Autodesk Fusion 360 part; units mm, degrees
(part 6 of 7)
  spline S19 degree 5 poles (-2.142617, 4.378906) (-2.143607, 4.374892) (-2.145571, 4.366867) (-2.148475, 4.354836) (-2.152259, 4.338808) (-2.156842, 4.318795) (-2.16128, 4.298806) (-2.165572, 4.27884) (-2.169716, 4.258897) (-2.173714, 4.23898) (-2.177564, 4.219088) (-2.181267, 4.199223) (-2.184822, 4.179387) (-2.188228, 4.15958) (-2.191486, 4.139805) (-2.194596, 4.12006) (-2.197556, 4.100349) (-2.200366, 4.080671) (-2.203027, 4.061028) (-2.205537, 4.041421) (-2.207897, 4.021851) (-2.210105, 4.002319) (-2.212162, 3.982827) (-2.214067, 3.963375) (-2.215819, 3.943964) (-2.217418, 3.924597) (-2.218864, 3.905273) (-2.220156, 3.885995) (-2.221294, 3.866763) (-2.222277, 3.847579) (-2.223104, 3.828444) (-2.223774, 3.80936) (-2.224287, 3.790328) (-2.224642, 3.771349) (-2.224838, 3.752425) (-2.224875, 3.733556) (-2.224754, 3.714745) (-2.224472, 3.695992) (-2.224029, 3.677299) (-2.223424, 3.658668) (-2.222655, 3.6401) (-2.221719, 3.621599) (-2.220614, 3.603166) (-2.219341, 3.584803) (-2.217898, 3.566511) (-2.216286, 3.548291) (-2.214508, 3.530142) (-2.212562, 3.512068) (-2.210445, 3.494069) (-2.208154, 3.47615) (-2.205679, 3.458317) (-2.203014, 3.440574) (-2.200153, 3.422926) (-2.197095, 3.405375) (-2.193845, 3.387919) (-2.190414, 3.370554) (-2.186811, 3.353277) (-2.183037, 3.336088) (-2.179085, 3.318994) (-2.174929, 3.30201) (-2.170533, 3.285156) (-2.165861, 3.268452) (-2.160894, 3.251912) (-2.155636, 3.235535) (-2.150128, 3.219302) (-2.144432, 3.203184) (-2.138596, 3.187157) (-2.132628, 3.171222) (-2.126466, 3.155419) (-2.119948, 3.139839) (-2.112853, 3.124607) (-2.106537, 3.112799) (-2.10136, 3.104201) (-2.097704, 3.098588) (-2.095824, 3.095812) knots -1 -1 -1 -1 -1 -1 -0.98571429 -0.97142857 -0.95714286 -0.94285714 -0.92857143 -0.91428571 -0.9 -0.88571429 -0.87142857 -0.85714286 -0.84285714 -0.82857143 -0.81428571 -0.8 -0.78571429 -0.77142857 -0.75714286 -0.74285714 -0.72857143 -0.71428571 -0.7 -0.68571429 -0.67142857 -0.65714286 -0.64285714 -0.62857143 -0.61428571 -0.6 -0.58571429 -0.57142857 -0.55714286 -0.54285714 -0.52857143 -0.51428571 -0.5 -0.48571429 -0.47142857 -0.45714286 -0.44285714 -0.42857143 -0.41428571 -0.4 -0.38571429 -0.37142857 -0.35714286 -0.34285714 -0.32857143 -0.31428571 -0.3 -0.28571429 -0.27142857 -0.25714286 -0.24285714 -0.22857143 -0.21428571 -0.2 -0.18571429 -0.17142857 -0.15714286 -0.14285714 -0.12857143 -0.11428571 -0.1 -0.08571429 -0.07142857 -0.05714286 -0.04285714 -0.02857143 -0.01428571 0 0 0 0 0 0
  line L19 (-2.095824, 3.095812) -> (-1.826023, 2.69728)
  arc A20 (-1.826023, 2.69728) -> (-2.409955, 2.1913) centre (0, 0) ccw
  line L20 (-2.409955, 2.1913) -> (-2.766034, 2.515072)
  spline S20 degree 5 poles (-2.766034, 2.515072) (-2.768515, 2.517327) (-2.77355, 2.521745) (-2.781324, 2.528093) (-2.792112, 2.536025) (-2.80618, 2.545216) (-2.820673, 2.553885) (-2.835439, 2.562233) (-2.850362, 2.570408) (-2.865395, 2.578465) (-2.880539, 2.586397) (-2.895823, 2.594159) (-2.911285, 2.601695) (-2.92695, 2.608965) (-2.942818, 2.615966) (-2.958875, 2.622717) (-2.975095, 2.629247) (-2.991453, 2.635592) (-3.00793, 2.641773) (-3.024518, 2.647799) (-3.041218, 2.653666) (-3.058034, 2.659367) (-3.074971, 2.664892) (-3.092032, 2.670235) (-3.109215, 2.675398) (-3.126515, 2.680386) (-3.143925, 2.685204) (-3.16144, 2.68986) (-3.179053, 2.694359) (-3.196764, 2.698702) (-3.21457, 2.70289) (-3.23247, 2.706922) (-3.250465, 2.710796) (-3.268553, 2.714512) (-3.286733, 2.718072) (-3.305001, 2.721476) (-3.323357, 2.724726) (-3.341797, 2.727825) (-3.360319, 2.730772) (-3.378921, 2.73357) (-3.397603, 2.736218) (-3.416363, 2.738717) (-3.435199, 2.741067) (-3.45411, 2.743268) (-3.473096, 2.74532) (-3.492154, 2.747225) (-3.511282, 2.748982) (-3.53048, 2.750593) (-3.549746, 2.752057) (-3.569078, 2.753376) (-3.588476, 2.75455) (-3.607939, 2.755578) (-3.627464, 2.756461) (-3.647051, 2.757199) (-3.666698, 2.757793) (-3.686405, 2.758242) (-3.70617, 2.758548) (-3.725991, 2.75871) (-3.745869, 2.758728) (-3.765801, 2.758604) (-3.785786, 2.758336) (-3.805825, 2.757925) (-3.825914, 2.757372) (-3.846055, 2.756677) (-3.866244, 2.755839) (-3.886481, 2.754858) (-3.906765, 2.753736) (-3.927094, 2.752472) (-3.947468, 2.751065) (-3.967886, 2.749518) (-3.988346, 2.747828) (-4.00475, 2.746364) (-4.017072, 2.745203) (-4.025295, 2.7444) (-4.029409, 2.743992) knots 0 0 0 0 0 0 0.01428571 0.02857143 0.04285714 0.05714286 0.07142857 0.08571429 0.1 0.11428571 0.12857143 0.14285714 0.15714286 0.17142857 0.18571429 0.2 0.21428571 0.22857143 0.24285714 0.25714286 0.27142857 0.28571429 0.3 0.31428571 0.32857143 0.34285714 0.35714286 0.37142857 0.38571429 0.4 0.41428571 0.42857143 0.44285714 0.45714286 0.47142857 0.48571429 0.5 0.51428571 0.52857143 0.54285714 0.55714286 0.57142857 0.58571429 0.6 0.61428571 0.62857143 0.64285714 0.65714286 0.67142857 0.68571429 0.7 0.71428571 0.72857143 0.74285714 0.75714286 0.77142857 0.78571429 0.8 0.81428571 0.82857143 0.84285714 0.85714286 0.87142857 0.88571429 0.9 0.91428571 0.92857143 0.94285714 0.95714286 0.97142857 0.98571429 1 1 1 1 1 1
  arc A21 (-4.029409, 2.743992) -> (-4.1699, 2.525384) centre (0, 0) ccw
  spline S21 degree 5 poles (-4.1699, 2.525384) (-4.168562, 2.521472) (-4.165876, 2.513659) (-4.161814, 2.501968) (-4.156332, 2.486438) (-4.149368, 2.467125) (-4.142295, 2.447909) (-4.13511, 2.428793) (-4.127815, 2.409775) (-4.12041, 2.390858) (-4.112895, 2.372043) (-4.10527, 2.35333) (-4.097536, 2.33472) (-4.089694, 2.316216) (-4.081743, 2.297818) (-4.073684, 2.279527) (-4.065518, 2.261345) (-4.057243, 2.243271) (-4.048862, 2.225308) (-4.040373, 2.207456) (-4.031778, 2.189717) (-4.023076, 2.172092) (-4.014268, 2.154582) (-4.005353, 2.137188) (-3.996333, 2.119912) (-3.987208, 2.102754) (-3.977977, 2.085716) (-3.968642, 2.0688) (-3.959202, 2.052006) (-3.949657, 2.035336) (-3.940007, 2.018792) (-3.930253, 2.002375) (-3.920395, 1.986087) (-3.910433, 1.969929) (-3.900367, 1.953902) (-3.890197, 1.938009) (-3.879925, 1.92225) (-3.869549, 1.906626) (-3.85907, 1.89114) (-3.848489, 1.875793) (-3.837803, 1.860589) (-3.827013, 1.845531) (-3.816119, 1.830622) (-3.805119, 1.815862) (-3.794016, 1.801254) (-3.78281, 1.786797) (-3.771502, 1.772491) (-3.760092, 1.758338) (-3.748581, 1.744341) (-3.736966, 1.730506) (-3.725243, 1.716841) (-3.713408, 1.703356) (-3.70146, 1.690056) (-3.689398, 1.676944) (-3.677227, 1.664016) (-3.664953, 1.651263) (-3.652581, 1.638677) (-3.640113, 1.626257) (-3.627547, 1.614013) (-3.614868, 1.601972) (-3.602057, 1.59017) (-3.589097, 1.578644) (-3.575976, 1.567415) (-3.562699, 1.556481) (-3.549289, 1.545803) (-3.535783, 1.535322) (-3.522209, 1.524994) (-3.508573, 1.514816) (-3.494845, 1.504853) (-3.480939, 1.49527) (-3.466735, 1.486292) (-3.455038, 1.479774) (-3.446034, 1.475339) (-3.439924, 1.472594) (-3.436842, 1.471275) knots -1 -1 -1 -1 -1 -1 -0.98571429 -0.97142857 -0.95714286 -0.94285714 -0.92857143 -0.91428571 -0.9 -0.88571429 -0.87142857 -0.85714286 -0.84285714 -0.82857143 -0.81428571 -0.8 -0.78571429 -0.77142857 -0.75714286 -0.74285714 -0.72857143 -0.71428571 -0.7 -0.68571429 -0.67142857 -0.65714286 -0.64285714 -0.62857143 -0.61428571 -0.6 -0.58571429 -0.57142857 -0.55714286 -0.54285714 -0.52857143 -0.51428571 -0.5 -0.48571429 -0.47142857 -0.45714286 -0.44285714 -0.42857143 -0.41428571 -0.4 -0.38571429 -0.37142857 -0.35714286 -0.34285714 -0.32857143 -0.31428571 -0.3 -0.28571429 -0.27142857 -0.25714286 -0.24285714 -0.22857143 -0.21428571 -0.2 -0.18571429 -0.17142857 -0.15714286 -0.14285714 -0.12857143 -0.11428571 -0.1 -0.08571429 -0.07142857 -0.05714286 -0.04285714 -0.02857143 -0.01428571 0 0 0 0 0 0
  line L21 (-3.436842, 1.471275) -> (-2.994408, 1.281873)
  circle A22 centre (0, 0) radius 1
  circle A23 centre (0, 0) radius 3
  dimension "d44" = 6
  constraint concentric A0 A23
  measures "d44" diameter of A23
extrude "Extrude12" add sketch "Sketch16" along normal blind 0.3 contours A23 picked at (2.318441, -0.198723) bodies 3
fillet "Fillet6" radius 0.1 1 faces at (-2.985092, 0.298704, 15.6) on bodies 3
move_body "Move3" bodies 3 to x (1, 0, 0) y (0, 1, 0) z (0, 0, 1) at (0, 0, -0.4)
combine "Combine1" operation add target body 2 tool bodies 3
sketch "Base Circle (2) (2)" plane through (0, 0, 0) normal (0, 0, 1) x (1, 0, 0)
  circle A0 centre (0, 0) radius 3.9087
  circle A1 centre (0, 0) radius 1
extrude "Extrude7" [suppressed]
sketch "Gear Tooth (2) (2)" plane through (0, 0, 0) normal (0, 0, 1) x (1, 0, 0)
  spline S0 degree 5 poles (4.423269, -0.748927) (4.427248, -0.7496) (4.43522, -0.750805) (4.447221, -0.752184) (4.463304, -0.753207) (4.483525, -0.753372) (4.503836, -0.752732) (4.524213, -0.751592) (4.544635, -0.750177) (4.565089, -0.748571) (4.585573, -0.746765) (4.606086, -0.744695) (4.626631, -0.742278) (4.647207, -0.739459) (4.667813, -0.736235) (4.688444, -0.732635) (4.709097, -0.728709) (4.729766, -0.724506) (4.750447, -0.720062) (4.771138, -0.715388) (4.791838, -0.710482) (4.812545, -0.705331) (4.83326, -0.699923) (4.85398, -0.694252) (4.874704, -0.68832) (4.89543, -0.682135) (4.916157, -0.675708) (4.936882, -0.669051) (4.957604, -0.66217) (4.978321, -0.65507) (4.999031, -0.647752) (5.019735, -0.640216) (5.04043, -0.632459) (5.061115, -0.624483) (5.081789, -0.616291) (5.10245, -0.607884) (5.123098, -0.599266) (5.143731, -0.590442) (5.164348, -0.581412) (5.184947, -0.57218) (5.205527, -0.562747) (5.226088, -0.553113) (5.246628, -0.54328) (5.267145, -0.533249) (5.28764, -0.523021) (5.30811, -0.512598) (5.328555, -0.501982) (5.348973, -0.491173) (5.369363, -0.480175) (5.389725, -0.468987) (5.410057, -0.457611) (5.430358, -0.446048) (5.450628, -0.4343) (5.470864, -0.422366) (5.491067, -0.410249) (5.511234, -0.397949) (5.531366, -0.385468) (5.55146, -0.372806) (5.571516, -0.359965) (5.591534, -0.346946) (5.611511, -0.333749) (5.631448, -0.320375) (5.651343, -0.306826) (5.671196, -0.293101) (5.691004, -0.279203) (5.710767, -0.265132) (5.730484, -0.250889) (5.750154, -0.236476) (5.769776, -0.221891) (5.789348, -0.207138) (5.808872, -0.192215) (5.824452, -0.180143) (5.836116, -0.171012) (5.843881, -0.164892) (5.847761, -0.161823) knots 0 0 0 0 0 0 0.01428571 0.02857143 0.04285714 0.05714286 0.07142857 0.08571429 0.1 0.11428571 0.12857143 0.14285714 0.15714286 0.17142857 0.18571429 0.2 0.21428571 0.22857143 0.24285714 0.25714286 0.27142857 0.28571429 0.3 0.31428571 0.32857143 0.34285714 0.35714286 0.37142857 0.38571429 0.4 0.41428571 0.42857143 0.44285714 0.45714286 0.47142857 0.48571429 0.5 0.51428571 0.52857143 0.54285714 0.55714286 0.57142857 0.58571429 0.6 0.61428571 0.62857143 0.64285714 0.65714286 0.67142857 0.68571429 0.7 0.71428571 0.72857143 0.74285714 0.75714286 0.77142857 0.78571429 0.8 0.81428571 0.82857143 0.84285714 0.85714286 0.87142857 0.88571429 0.9 0.91428571 0.92857143 0.94285714 0.95714286 0.97142857 0.98571429 1 1 1 1 1 1
  spline S1 degree 5 poles (4.423269, 0.748927) (4.427248, 0.7496) (4.43522, 0.750805) (4.447221, 0.752184) (4.463304, 0.753207) (4.483525, 0.753372) (4.503836, 0.752732) (4.524213, 0.751592) (4.544635, 0.750177) (4.565089, 0.748571) (4.585573, 0.746765) (4.606086, 0.744695) (4.626631, 0.742278) (4.647207, 0.739459) (4.667813, 0.736235) (4.688444, 0.732635) (4.709097, 0.728709) (4.729766, 0.724506) (4.750447, 0.720062) (4.771138, 0.715388) (4.791838, 0.710482) (4.812545, 0.705331) (4.83326, 0.699923) (4.85398, 0.694252) (4.874704, 0.68832) (4.89543, 0.682135) (4.916157, 0.675708) (4.936882, 0.669051) (4.957604, 0.66217) (4.978321, 0.65507) (4.999031, 0.647752) (5.019735, 0.640216) (5.04043, 0.632459) (5.061115, 0.624483) (5.081789, 0.616291) (5.10245, 0.607884) (5.123098, 0.599266) (5.143731, 0.590442) (5.164348, 0.581412) (5.184947, 0.57218) (5.205527, 0.562747) (5.226088, 0.553113) (5.246628, 0.54328) (5.267145, 0.533249) (5.28764, 0.523021) (5.30811, 0.512598) (5.328555, 0.501982) (5.348973, 0.491173) (5.369363, 0.480175) (5.389725, 0.468987) (5.410057, 0.457611) (5.430358, 0.446048) (5.450628, 0.4343) (5.470864, 0.422366) (5.491067, 0.410249) (5.511234, 0.397949) (5.531366, 0.385468) (5.55146, 0.372806) (5.571516, 0.359965) (5.591534, 0.346946) (5.611511, 0.333749) (5.631448, 0.320375) (5.651343, 0.306826) (5.671196, 0.293101) (5.691004, 0.279203) (5.710767, 0.265132) (5.730484, 0.250889) (5.750154, 0.236476) (5.769776, 0.221891) (5.789348, 0.207138) (5.808872, 0.192215) (5.824452, 0.180143) (5.836116, 0.171012) (5.843881, 0.164892) (5.847761, 0.161823) knots 0 0 0 0 0 0 0.01428571 0.02857143 0.04285714 0.05714286 0.07142857 0.08571429 0.1 0.11428571 0.12857143 0.14285714 0.15714286 0.17142857 0.18571429 0.2 0.21428571 0.22857143 0.24285714 0.25714286 0.27142857 0.28571429 0.3 0.31428571 0.32857143 0.34285714 0.35714286 0.37142857 0.38571429 0.4 0.41428571 0.42857143 0.44285714 0.45714286 0.47142857 0.48571429 0.5 0.51428571 0.52857143 0.54285714 0.55714286 0.57142857 0.58571429 0.6 0.61428571 0.62857143 0.64285714 0.65714286 0.67142857 0.68571429 0.7 0.71428571 0.72857143 0.74285714 0.75714286 0.77142857 0.78571429 0.8 0.81428571 0.82857143 0.84285714 0.85714286 0.87142857 0.88571429 0.9 0.91428571 0.92857143 0.94285714 0.95714286 0.97142857 0.98571429 1 1 1 1 1 1
  arc A0 (5.847761, -0.161823) -> (5.847761, 0.161823) centre (0, 0) ccw
  line L0 (3.84399, -0.650846) -> (4.423269, -0.748927)
  line L1 (3.84399, 0.650846) -> (4.423269, 0.748927)
  line L2 (3.84399, -0.650846) -> (3.84399, 0.650846)
  point P0 (4.521581, -0.751683)
  point P1 (4.62174, -0.742791)
  point P2 (4.723012, -0.725845)
  point P3 (4.82507, -0.702027)
  point P4 (4.927679, -0.671978)
  point P5 (5.030643, -0.636099)
  point P6 (5.133785, -0.594669)
  point P7 (5.236942, -0.547891)
  point P8 (5.339959, -0.495919)
  point P9 (5.442684, -0.438878)
  point P10 (5.54497, -0.376867)
  point P11 (5.646673, -0.309973)
  point P12 (5.747651, -0.23827)
  point P13 (4.521581, 0.751683)
  point P14 (4.62174, 0.742791)
  point P15 (4.723012, 0.725845)
  point P16 (4.82507, 0.702027)
  point P17 (4.927679, 0.671978)
  point P18 (5.030643, 0.636099)
  point P19 (5.133785, 0.594669)
  point P20 (5.236942, 0.547891)
  point P21 (5.339959, 0.495919)
  point P22 (5.442684, 0.438878)
  point P23 (5.54497, 0.376867)
  point P24 (5.646673, 0.309973)
  point P25 (5.747651, 0.23827)
extrude "Extrude8" [suppressed]
pattern_circular "C-Pattern3" [suppressed]
sketch "Diametrial Pitch Circle (2) (2)" plane through (0, 0, 0) normal (0, 0, 1) x (1, 0, 0)
  circle A0 centre (0, 0) radius 4.95 construction
move_body "Move1" [suppressed]
sketch "Sketch12" plane through (0, 0, 15.5) normal (0, 0, 1) x (-1, 0, 0)
  arc A0 (-3.594841, 1.534618) -> (-3.85385, 0.652515) centre (0, 0) ccw
  line L0 (-3.85385, 0.652515) -> (-4.423269, 0.748927)
  spline S0 degree 5 poles (-4.423269, 0.748927) (-4.427248, 0.7496) (-4.43522, 0.750805) (-4.447221, 0.752184) (-4.463304, 0.753207) (-4.483525, 0.753372) (-4.503836, 0.752732) (-4.524213, 0.751592) (-4.544635, 0.750177) (-4.565089, 0.748571) (-4.585573, 0.746765) (-4.606086, 0.744695) (-4.626631, 0.742278) (-4.647207, 0.739459) (-4.667813, 0.736235) (-4.688444, 0.732635) (-4.709097, 0.728709) (-4.729766, 0.724506) (-4.750447, 0.720062) (-4.771138, 0.715388) (-4.791838, 0.710482) (-4.812545, 0.705331) (-4.83326, 0.699923) (-4.85398, 0.694252) (-4.874704, 0.68832) (-4.89543, 0.682135) (-4.916157, 0.675708) (-4.936882, 0.669051) (-4.957604, 0.66217) (-4.978321, 0.65507) (-4.999031, 0.647752) (-5.019735, 0.640216) (-5.04043, 0.632459) (-5.061115, 0.624483) (-5.081789, 0.616291) (-5.10245, 0.607884) (-5.123098, 0.599266) (-5.143731, 0.590442) (-5.164348, 0.581412) (-5.184947, 0.57218) (-5.205527, 0.562747) (-5.226088, 0.553113) (-5.246628, 0.54328) (-5.267145, 0.533249) (-5.28764, 0.523021) (-5.30811, 0.512598) (-5.328555, 0.501982) (-5.348973, 0.491173) (-5.369363, 0.480175) (-5.389725, 0.468987) (-5.410057, 0.457611) (-5.430358, 0.446048) (-5.450628, 0.4343) (-5.470864, 0.422366) (-5.491067, 0.410249) (-5.511234, 0.397949) (-5.531366, 0.385468) (-5.55146, 0.372806) (-5.571516, 0.359965) (-5.591534, 0.346946) (-5.611511, 0.333749) (-5.631448, 0.320375) (-5.651343, 0.306826) (-5.671196, 0.293101) (-5.691004, 0.279203) (-5.710767, 0.265132) (-5.730484, 0.250889) (-5.750154, 0.236476) (-5.769776, 0.221891) (-5.789348, 0.207138) (-5.808872, 0.192215) (-5.824452, 0.180143) (-5.836116, 0.171012) (-5.843881, 0.164892) (-5.847761, 0.161823) knots 0 0 0 0 0 0 0.01428571 0.02857143 0.04285714 0.05714286 0.07142857 0.08571429 0.1 0.11428571 0.12857143 0.14285714 0.15714286 0.17142857 0.18571429 0.2 0.21428571 0.22857143 0.24285714 0.25714286 0.27142857 0.28571429 0.3 0.31428571 0.32857143 0.34285714 0.35714286 0.37142857 0.38571429 0.4 0.41428571 0.42857143 0.44285714 0.45714286 0.47142857 0.48571429 0.5 0.51428571 0.52857143 0.54285714 0.55714286 0.57142857 0.58571429 0.6 0.61428571 0.62857143 0.64285714 0.65714286 0.67142857 0.68571429 0.7 0.71428571 0.72857143 0.74285714 0.75714286 0.77142857 0.78571429 0.8 0.81428571 0.82857143 0.84285714 0.85714286 0.87142857 0.88571429 0.9 0.91428571 0.92857143 0.94285714 0.95714286 0.97142857 0.98571429 1 1 1 1 1 1
  arc A1 (-5.847761, 0.161823) -> (-5.847761, -0.161823) centre (0, 0) ccw
  spline S1 degree 5 poles (-5.847761, -0.161823) (-5.843881, -0.164892) (-5.836116, -0.171012) (-5.824452, -0.180143) (-5.808872, -0.192215) (-5.789348, -0.207138) (-5.769776, -0.221891) (-5.750154, -0.236476) (-5.730484, -0.250889) (-5.710767, -0.265132) (-5.691004, -0.279203) (-5.671196, -0.293101) (-5.651343, -0.306826) (-5.631448, -0.320375) (-5.611511, -0.333749) (-5.591534, -0.346946) (-5.571516, -0.359965) (-5.55146, -0.372806) (-5.531366, -0.385468) (-5.511234, -0.397949) (-5.491067, -0.410249) (-5.470864, -0.422366) (-5.450628, -0.4343) (-5.430358, -0.446048) (-5.410057, -0.457611) (-5.389725, -0.468987) (-5.369363, -0.480175) (-5.348973, -0.491173) (-5.328555, -0.501982) (-5.30811, -0.512598) (-5.28764, -0.523021) (-5.267145, -0.533249) (-5.246628, -0.54328) (-5.226088, -0.553113) (-5.205527, -0.562747) (-5.184947, -0.57218) (-5.164348, -0.581412) (-5.143731, -0.590442) (-5.123098, -0.599266) (-5.10245, -0.607884) (-5.081789, -0.616291) (-5.061115, -0.624483) (-5.04043, -0.632459) (-5.019735, -0.640216) (-4.999031, -0.647752) (-4.978321, -0.65507) (-4.957604, -0.66217) (-4.936882, -0.669051) (-4.916157, -0.675708) (-4.89543, -0.682135) (-4.874704, -0.68832) (-4.85398, -0.694252) (-4.83326, -0.699923) (-4.812545, -0.705331) (-4.791838, -0.710482) (-4.771138, -0.715388) (-4.750447, -0.720062) (-4.729766, -0.724506) (-4.709097, -0.728709) (-4.688444, -0.732635) (-4.667813, -0.736235) (-4.647207, -0.739459) (-4.626631, -0.742278) (-4.606086, -0.744695) (-4.585573, -0.746765) (-4.565089, -0.748571) (-4.544635, -0.750177) (-4.524213, -0.751592) (-4.503836, -0.752732) (-4.483525, -0.753372) (-4.463304, -0.753207) (-4.447221, -0.752184) (-4.43522, -0.750805) (-4.427248, -0.7496) (-4.423269, -0.748927) knots -1 -1 -1 -1 -1 -1 -0.98571429 -0.97142857 -0.95714286 -0.94285714 -0.92857143 -0.91428571 -0.9 -0.88571429 -0.87142857 -0.85714286 -0.84285714 -0.82857143 -0.81428571 -0.8 -0.78571429 -0.77142857 -0.75714286 -0.74285714 -0.72857143 -0.71428571 -0.7 -0.68571429 -0.67142857 -0.65714286 -0.64285714 -0.62857143 -0.61428571 -0.6 -0.58571429 -0.57142857 -0.55714286 -0.54285714 -0.52857143 -0.51428571 -0.5 -0.48571429 -0.47142857 -0.45714286 -0.44285714 -0.42857143 -0.41428571 -0.4 -0.38571429 -0.37142857 -0.35714286 -0.34285714 -0.32857143 -0.31428571 -0.3 -0.28571429 -0.27142857 -0.25714286 -0.24285714 -0.22857143 -0.21428571 -0.2 -0.18571429 -0.17142857 -0.15714286 -0.14285714 -0.12857143 -0.11428571 -0.1 -0.08571429 -0.07142857 -0.05714286 -0.04285714 -0.02857143 -0.01428571 0 0 0 0 0 0
  line L1 (-4.423269, -0.748927) -> (-3.85385, -0.652515)
  arc A2 (-3.85385, -0.652515) -> (-3.594841, -1.534618) centre (0, 0) ccw
  line L2 (-3.594841, -1.534618) -> (-4.125991, -1.761363)
  spline S2 degree 5 poles (-4.125991, -1.761363) (-4.129703, -1.762947) (-4.13706, -1.766244) (-4.147902, -1.771572) (-4.161985, -1.779406) (-4.179085, -1.7902) (-4.195826, -1.801719) (-4.212352, -1.813695) (-4.228766, -1.825926) (-4.245105, -1.838336) (-4.261361, -1.850929) (-4.277499, -1.863761) (-4.293475, -1.876901) (-4.309261, -1.890397) (-4.324852, -1.90425) (-4.340263, -1.918432) (-4.355514, -1.932901) (-4.370629, -1.947611) (-4.385625, -1.962531) (-4.400505, -1.977649) (-4.415266, -1.992968) (-4.429902, -2.008496) (-4.444404, -2.024244) (-4.458769, -2.040217) (-4.472996, -2.056412) (-4.487088, -2.072821) (-4.50105, -2.089433) (-4.514886, -2.106239) (-4.528598, -2.12323) (-4.542188, -2.140403) (-4.555654, -2.157756) (-4.568996, -2.17529) (-4.582212, -2.193003) (-4.595302, -2.210896) (-4.608265, -2.228966) (-4.621101, -2.247208) (-4.633812, -2.265621) (-4.646399, -2.2842) (-4.658861, -2.302942) (-4.671199, -2.321845) (-4.683412, -2.340908) (-4.6955, -2.360128) (-4.707463, -2.379505) (-4.719301, -2.399036) (-4.731012, -2.418721) (-4.742598, -2.438556) (-4.754057, -2.45854) (-4.765391, -2.478672) (-4.776598, -2.498948) (-4.787679, -2.519369) (-4.798633, -2.539931) (-4.80946, -2.560634) (-4.82016, -2.581476) (-4.830732, -2.602456) (-4.841177, -2.623572) (-4.851493, -2.644822) (-4.861681, -2.666206) (-4.87174, -2.687721) (-4.88167, -2.709367) (-4.891471, -2.731142) (-4.901142, -2.753045) (-4.910683, -2.775074) (-4.920095, -2.797229) (-4.929376, -2.819507) (-4.938526, -2.841908) (-4.947545, -2.864431) (-4.956431, -2.887072) (-4.965186, -2.909832) (-4.973808, -2.932709) (-4.982297, -2.955703) (-4.990654, -2.978812) (-4.997234, -2.997391) (-5.002109, -3.011378) (-5.005333, -3.020725) (-5.006938, -3.025404) knots 0 0 0 0 0 0 0.01428571 0.02857143 0.04285714 0.05714286 0.07142857 0.08571429 0.1 0.11428571 0.12857143 0.14285714 0.15714286 0.17142857 0.18571429 0.2 0.21428571 0.22857143 0.24285714 0.25714286 0.27142857 0.28571429 0.3 0.31428571 0.32857143 0.34285714 0.35714286 0.37142857 0.38571429 0.4 0.41428571 0.42857143 0.44285714 0.45714286 0.47142857 0.48571429 0.5 0.51428571 0.52857143 0.54285714 0.55714286 0.57142857 0.58571429 0.6 0.61428571 0.62857143 0.64285714 0.65714286 0.67142857 0.68571429 0.7 0.71428571 0.72857143 0.74285714 0.75714286 0.77142857 0.78571429 0.8 0.81428571 0.82857143 0.84285714 0.85714286 0.87142857 0.88571429 0.9 0.91428571 0.92857143 0.94285714 0.95714286 0.97142857 0.98571429 1 1 1 1 1 1
  arc A3 (-5.006938, -3.025404) -> (-4.831962, -3.297673) centre (0, 0) ccw
  spline S3 degree 5 poles (-4.831962, -3.297673) (-4.827038, -3.298156) (-4.817197, -3.299107) (-4.802449, -3.300482) (-4.782815, -3.302215) (-4.758323, -3.304214) (-4.73388, -3.306043) (-4.709489, -3.307704) (-4.685149, -3.309195) (-4.660862, -3.310517) (-4.636629, -3.31167) (-4.612451, -3.312652) (-4.58833, -3.313465) (-4.564268, -3.314107) (-4.540266, -3.314579) (-4.516325, -3.314881) (-4.492446, -3.315011) (-4.468631, -3.314971) (-4.444881, -3.314758) (-4.421198, -3.314374) (-4.397582, -3.313818) (-4.374036, -3.31309) (-4.35056, -3.312188) (-4.327156, -3.311113) (-4.303827, -3.309865) (-4.280572, -3.308442) (-4.257394, -3.306846) (-4.234294, -3.305074) (-4.211274, -3.303128) (-4.188335, -3.301006) (-4.165479, -3.298707) (-4.142709, -3.296231) (-4.120025, -3.293577) (-4.097429, -3.290745) (-4.074924, -3.287733) (-4.052511, -3.284542) (-4.03019, -3.281172) (-4.007965, -3.277622) (-3.985836, -3.273891) (-3.963807, -3.269977) (-3.941881, -3.265879) (-3.920059, -3.261594) (-3.898346, -3.25712) (-3.876743, -3.252457) (-3.855251, -3.247604) (-3.833872, -3.242564) (-3.812606, -3.237336) (-3.791454, -3.231921) (-3.770419, -3.226317) (-3.749508, -3.220518) (-3.728728, -3.214515) (-3.708086, -3.208302) (-3.68759, -3.201871) (-3.66724, -3.195221) (-3.647035, -3.188358) (-3.626969, -3.181295) (-3.607036, -3.17404) (-3.587235, -3.166597) (-3.567575, -3.158959) (-3.548078, -3.151096) (-3.528775, -3.14297) (-3.509698, -3.134542) (-3.490864, -3.125789) (-3.472274, -3.116715) (-3.453898, -3.107367) (-3.43569, -3.097811) (-3.417614, -3.088104) (-3.399669, -3.078254) (-3.381911, -3.068196) (-3.364477, -3.057753) (-3.347556, -3.046682) (-3.334579, -3.037126) (-3.325229, -3.029478) (-3.319174, -3.024155) (-3.316191, -3.021437) knots -1 -1 -1 -1 -1 -1 -0.98571429 -0.97142857 -0.95714286 -0.94285714 -0.92857143 -0.91428571 -0.9 -0.88571429 -0.87142857 -0.85714286 -0.84285714 -0.82857143 -0.81428571 -0.8 -0.78571429 -0.77142857 -0.75714286 -0.74285714 -0.72857143 -0.71428571 -0.7 -0.68571429 -0.67142857 -0.65714286 -0.64285714 -0.62857143 -0.61428571 -0.6 -0.58571429 -0.57142857 -0.55714286 -0.54285714 -0.52857143 -0.51428571 -0.5 -0.48571429 -0.47142857 -0.45714286 -0.44285714 -0.42857143 -0.41428571 -0.4 -0.38571429 -0.37142857 -0.35714286 -0.34285714 -0.32857143 -0.31428571 -0.3 -0.28571429 -0.27142857 -0.25714286 -0.24285714 -0.22857143 -0.21428571 -0.2 -0.18571429 -0.17142857 -0.15714286 -0.14285714 -0.12857143 -0.11428571 -0.1 -0.08571429 -0.07142857 -0.05714286 -0.04285714 -0.02857143 -0.01428571 0 0 0 0 0 0
  line L3 (-3.316191, -3.021437) -> (-2.889288, -2.632479)
  arc A4 (-2.889288, -2.632479) -> (-2.194496, -3.234521) centre (0, 0) ccw
  line L4 (-2.194496, -3.234521) -> (-2.51874, -3.712432)
  spline S4 degree 5 poles (-2.51874, -3.712432) (-2.521006, -3.715771) (-2.525413, -3.722523) (-2.531653, -3.732866) (-2.539265, -3.747071) (-2.547815, -3.765395) (-2.55567, -3.784138) (-2.563098, -3.803147) (-2.570294, -3.822311) (-2.57733, -3.841584) (-2.584197, -3.860967) (-2.590836, -3.880486) (-2.597172, -3.900178) (-2.603155, -3.920066) (-2.608782, -3.940149) (-2.614078, -3.960411) (-2.619086, -3.980829) (-2.623849, -4.001376) (-2.628398, -4.022034) (-2.632742, -4.042797) (-2.636878, -4.063664) (-2.640795, -4.08464) (-2.644481, -4.105729) (-2.64793, -4.126932) (-2.651143, -4.148248) (-2.654127, -4.169671) (-2.656891, -4.191194) (-2.659445, -4.212812) (-2.661794, -4.23452) (-2.663942, -4.256314) (-2.665889, -4.278193) (-2.667634, -4.300156) (-2.669175, -4.322203) (-2.670513, -4.344332) (-2.671649, -4.366541) (-2.672585, -4.388828) (-2.673324, -4.41119) (-2.673868, -4.433624) (-2.674219, -4.456128) (-2.674378, -4.478701) (-2.674347, -4.501341) (-2.674125, -4.524045) (-2.673713, -4.546814) (-2.673111, -4.569644) (-2.672322, -4.592536) (-2.671344, -4.615486) (-2.67018, -4.638493) (-2.668831, -4.661556) (-2.667296, -4.684673) (-2.665578, -4.707842) (-2.663677, -4.731063) (-2.661592, -4.754333) (-2.659325, -4.777651) (-2.656877, -4.801016) (-2.654247, -4.824427) (-2.651437, -4.847881) (-2.648446, -4.871378) (-2.645277, -4.894916) (-2.641928, -4.918495) (-2.6384, -4.942112) (-2.634695, -4.965766) (-2.630812, -4.989457) (-2.626751, -5.013183) (-2.622514, -5.036942) (-2.618101, -5.060734) (-2.613511, -5.084557) (-2.608746, -5.108409) (-2.603806, -5.132289) (-2.598691, -5.156195) (-2.593402, -5.180128) (-2.587938, -5.204087) (-2.583428, -5.223274) (-2.579968, -5.237676) (-2.577627, -5.247283) (-2.576447, -5.252087) knots 0 0 0 0 0 0 0.01428571 0.02857143 0.04285714 0.05714286 0.07142857 0.08571429 0.1 0.11428571 0.12857143 0.14285714 0.15714286 0.17142857 0.18571429 0.2 0.21428571 0.22857143 0.24285714 0.25714286 0.27142857 0.28571429 0.3 0.31428571 0.32857143 0.34285714 0.35714286 0.37142857 0.38571429 0.4 0.41428571 0.42857143 0.44285714 0.45714286 0.47142857 0.48571429 0.5 0.51428571 0.52857143 0.54285714 0.55714286 0.57142857 0.58571429 0.6 0.61428571 0.62857143 0.64285714 0.65714286 0.67142857 0.68571429 0.7 0.71428571 0.72857143 0.74285714 0.75714286 0.77142857 0.78571429 0.8 0.81428571 0.82857143 0.84285714 0.85714286 0.87142857 0.88571429 0.9 0.91428571 0.92857143 0.94285714 0.95714286 0.97142857 0.98571429 1 1 1 1 1 1
  arc A5 (-2.576447, -5.252087) -> (-2.282049, -5.386534) centre (0, 0) ccw
  spline S5 degree 5 poles (-2.282049, -5.386534) (-2.277645, -5.38428) (-2.268852, -5.379758) (-2.255702, -5.372942) (-2.238248, -5.363785) (-2.216563, -5.352225) (-2.195012, -5.340549) (-2.173595, -5.32876) (-2.152312, -5.316855) (-2.131166, -5.304837) (-2.110156, -5.292705) (-2.089285, -5.28046) (-2.068554, -5.268103) (-2.047965, -5.255634) (-2.027517, -5.243054) (-2.007214, -5.230365) (-1.987056, -5.217565) (-1.967043, -5.204655) (-1.947178, -5.191637) (-1.927462, -5.178509) (-1.907896, -5.165274) (-1.888481, -5.151931) (-1.86922, -5.13848) (-1.850113, -5.124923) (-1.831161, -5.11126) (-1.812367, -5.097491) (-1.793732, -5.083616) (-1.775257, -5.069638) (-1.756943, -5.055555) (-1.738793, -5.041368) (-1.720808, -5.027077) (-1.702991, -5.012683) (-1.685343, -4.998187) (-1.667866, -4.983588) (-1.650562, -4.968888) (-1.633431, -4.954086) (-1.616476, -4.939183) (-1.599698, -4.924181) (-1.5831, -4.909078) (-1.566684, -4.893876) (-1.550453, -4.878574) (-1.534413, -4.863172) (-1.518565, -4.847669) (-1.502913, -4.832067) (-1.487456, -4.816365) (-1.472196, -4.800566) (-1.457132, -4.784671) (-1.442265, -4.76868) (-1.4276, -4.752593) (-1.413144, -4.736409) (-1.398907, -4.720125) (-1.384902, -4.703738) (-1.371136, -4.687246) (-1.357612, -4.67065) (-1.344325, -4.653954) (-1.331263, -4.637163) (-1.318416, -4.620283) (-1.305782, -4.603317) (-1.293373, -4.586262) (-1.281222, -4.569107) (-1.269377, -4.551835) (-1.257884, -4.53443) (-1.246772, -4.516885) (-1.236039, -4.499201) (-1.225635, -4.481402) (-1.215483, -4.463519) (-1.205525, -4.44558) (-1.195754, -4.427592) (-1.186252, -4.40953) (-1.177232, -4.391319) (-1.168982, -4.372858) (-1.163232, -4.357803) (-1.159501, -4.346314) (-1.157285, -4.338562) (-1.156245, -4.334663) knots -1 -1 -1 -1 -1 -1 -0.98571429 -0.97142857 -0.95714286 -0.94285714 -0.92857143 -0.91428571 -0.9 -0.88571429 -0.87142857 -0.85714286 -0.84285714 -0.82857143 -0.81428571 -0.8 -0.78571429 -0.77142857 -0.75714286 -0.74285714 -0.72857143 -0.71428571 -0.7 -0.68571429 -0.67142857 -0.65714286 -0.64285714 -0.62857143 -0.61428571 -0.6 -0.58571429 -0.57142857 -0.55714286 -0.54285714 -0.52857143 -0.51428571 -0.5 -0.48571429 -0.47142857 -0.45714286 -0.44285714 -0.42857143 -0.41428571 -0.4 -0.38571429 -0.37142857 -0.35714286 -0.34285714 -0.32857143 -0.31428571 -0.3 -0.28571429 -0.27142857 -0.25714286 -0.24285714 -0.22857143 -0.21428571 -0.2 -0.18571429 -0.17142857 -0.15714286 -0.14285714 -0.12857143 -0.11428571 -0.1 -0.08571429 -0.07142857 -0.05714286 -0.04285714 -0.02857143 -0.01428571 0 0 0 0 0 0
  line L5 (-1.156245, -4.334663) -> (-1.007398, -3.77665)
  arc A6 (-1.007398, -3.77665) -> (-0.097414, -3.907486) centre (0, 0) ccw
  line L6 (-0.097414, -3.907486) -> (-0.111807, -4.48483)
  spline S6 degree 5 poles (-0.111807, -4.48483) (-0.111907, -4.488864) (-0.111965, -4.496927) (-0.111622, -4.509002) (-0.110346, -4.525067) (-0.107632, -4.545105) (-0.104108, -4.565119) (-0.100079, -4.585126) (-0.095772, -4.605138) (-0.091271, -4.625156) (-0.086569, -4.645175) (-0.0816, -4.665184) (-0.076284, -4.685175) (-0.070566, -4.705141) (-0.064442, -4.725078) (-0.057943, -4.744987) (-0.051117, -4.764871) (-0.044015, -4.784731) (-0.036673, -4.80457) (-0.029103, -4.824385) (-0.0213, -4.844176) (-0.013255, -4.86394) (-0.004955, -4.883674) (0.003608, -4.903375) (0.012429, -4.923044) (0.021501, -4.94268) (0.030812, -4.962281) (0.040351, -4.981848) (0.05011, -5.001379) (0.060086, -5.020875) (0.070277, -5.040333) (0.080684, -5.059753) (0.091306, -5.079134) (0.102145, -5.098473) (0.113196, -5.117771) (0.124458, -5.137026) (0.135926, -5.156237) (0.147597, -5.175404) (0.159469, -5.194526) (0.171539, -5.213601) (0.183805, -5.23263) (0.196267, -5.25161) (0.208923, -5.270541) (0.221772, -5.289423) (0.234812, -5.308253) (0.248042, -5.327031) (0.26146, -5.345757) (0.275064, -5.364429) (0.288853, -5.383047) (0.302825, -5.401609) (0.316978, -5.420115) (0.331313, -5.438565) (0.345826, -5.456956) (0.360518, -5.475288) (0.375387, -5.49356) (0.390432, -5.511772) (0.405651, -5.529922) (0.421043, -5.54801) (0.436608, -5.566035) (0.452344, -5.583996) (0.46825, -5.601892) (0.484325, -5.619722) (0.500567, -5.637487) (0.516977, -5.655184) (0.533553, -5.672813) (0.550293, -5.690372) (0.567197, -5.707862) (0.584264, -5.72528) (0.601492, -5.742626) (0.618881, -5.7599) (0.63643, -5.777102) (0.650597, -5.790805) (0.661294, -5.80105) (0.668458, -5.807865) (0.672048, -5.811269) knots 0 0 0 0 0 0 0.01428571 0.02857143 0.04285714 0.05714286 0.07142857 0.08571429 0.1 0.11428571 0.12857143 0.14285714 0.15714286 0.17142857 0.18571429 0.2 0.21428571 0.22857143 0.24285714 0.25714286 0.27142857 0.28571429 0.3 0.31428571 0.32857143 0.34285714 0.35714286 0.37142857 0.38571429 0.4 0.41428571 0.42857143 0.44285714 0.45714286 0.47142857 0.48571429 0.5 0.51428571 0.52857143 0.54285714 0.55714286 0.57142857 0.58571429 0.6 0.61428571 0.62857143 0.64285714 0.65714286 0.67142857 0.68571429 0.7 0.71428571 0.72857143 0.74285714 0.75714286 0.77142857 0.78571429 0.8 0.81428571 0.82857143 0.84285714 0.85714286 0.87142857 0.88571429 0.9 0.91428571 0.92857143 0.94285714 0.95714286 0.97142857 0.98571429 1 1 1 1 1 1
  arc A7 (0.672048, -5.811269) -> (0.992399, -5.76521) centre (0, 0) ccw
  spline S7 degree 5 poles (0.992399, -5.76521) (0.994884, -5.760932) (0.999837, -5.752375) (1.007215, -5.739531) (1.016948, -5.722391) (1.02894, -5.700942) (1.040758, -5.679469) (1.052401, -5.657972) (1.063869, -5.636451) (1.075161, -5.614908) (1.086276, -5.593343) (1.097213, -5.571758) (1.107973, -5.550155) (1.118553, -5.528534) (1.128953, -5.506897) (1.139173, -5.485245) (1.149211, -5.463578) (1.159067, -5.441898) (1.16874, -5.420207) (1.178229, -5.398504) (1.187534, -5.376791) (1.196652, -5.35507) (1.205584, -5.333341) (1.214329, -5.311606) (1.222885, -5.289866) (1.231251, -5.268122) (1.239427, -5.246375) (1.247412, -5.224627) (1.255205, -5.202878) (1.262803, -5.181131) (1.270207, -5.159386) (1.277414, -5.137644) (1.284423, -5.115908) (1.291233, -5.094178) (1.297843, -5.072455) (1.304251, -5.050742) (1.310458, -5.029038) (1.316461, -5.007347) (1.32226, -4.985668) (1.327851, -4.964004) (1.333232, -4.942356) (1.338399, -4.920726) (1.34335, -4.899117) (1.348082, -4.877529) (1.352596, -4.855964) (1.356892, -4.834422) (1.360971, -4.812906) (1.364832, -4.791416) (1.368472, -4.769954) (1.371884, -4.748524) (1.375056, -4.727128) (1.377979, -4.705771) (1.380644, -4.684455) (1.383048, -4.663182) (1.385199, -4.641952) (1.38711, -4.620765) (1.388792, -4.599619) (1.390247, -4.578516) (1.391466, -4.557459) (1.392413, -4.536458) (1.39304, -4.515524) (1.393299, -4.494669) (1.393161, -4.473901) (1.392629, -4.453222) (1.391759, -4.432623) (1.390631, -4.412091) (1.38931, -4.391616) (1.387804, -4.371201) (1.386033, -4.350869) (1.383776, -4.330673) (1.380735, -4.310681) (1.377433, -4.294908) (1.374361, -4.283225) (1.372034, -4.275506) (1.370801, -4.271663) knots -1 -1 -1 -1 -1 -1 -0.98571429 -0.97142857 -0.95714286 -0.94285714 -0.92857143 -0.91428571 -0.9 -0.88571429 -0.87142857 -0.85714286 -0.84285714 -0.82857143 -0.81428571 -0.8 -0.78571429 -0.77142857 -0.75714286 -0.74285714 -0.72857143 -0.71428571 -0.7 -0.68571429 -0.67142857 -0.65714286 -0.64285714 -0.62857143 -0.61428571 -0.6 -0.58571429 -0.57142857 -0.55714286 -0.54285714 -0.52857143 -0.51428571 -0.5 -0.48571429 -0.47142857 -0.45714286 -0.44285714 -0.42857143 -0.41428571 -0.4 -0.38571429 -0.37142857 -0.35714286 -0.34285714 -0.32857143 -0.31428571 -0.3 -0.28571429 -0.27142857 -0.25714286 -0.24285714 -0.22857143 -0.21428571 -0.2 -0.18571429 -0.17142857 -0.15714286 -0.14285714 -0.12857143 -0.11428571 -0.1 -0.08571429 -0.07142857 -0.05714286 -0.04285714 -0.02857143 -0.01428571 0 0 0 0 0 0
  line L7 (1.370801, -4.271663) -> (1.194334, -3.721761)
  arc A8 (1.194334, -3.721761) -> (2.030597, -3.339852) centre (0, 0) ccw
  line L8 (2.030597, -3.339852) -> (2.330624, -3.833326)
  spline S8 degree 5 poles (2.330624, -3.833326) (2.332721, -3.836775) (2.337031, -3.843588) (2.343848, -3.853561) (2.353607, -3.866386) (2.366724, -3.881776) (2.380509, -3.896707) (2.394714, -3.91136) (2.409157, -3.925867) (2.423766, -3.940274) (2.438545, -3.954572) (2.453543, -3.968719) (2.468823, -3.982663) (2.484428, -3.996367) (2.500358, -4.009828) (2.516589, -4.023064) (2.533081, -4.036101) (2.549793, -4.048969) (2.566695, -4.061688) (2.583777, -4.074265) (2.60104, -4.086696) (2.618493, -4.098973) (2.636145, -4.111086) (2.654, -4.123032) (2.672055, -4.134809) (2.690302, -4.146423) (2.708732, -4.157878) (2.727336, -4.169181) (2.746105, -4.180336) (2.765038, -4.191344) (2.784131, -4.202204) (2.803385, -4.212914) (2.822799, -4.223475) (2.842372, -4.233885) (2.862102, -4.244144) (2.881986, -4.254254) (2.90202, -4.264215) (2.922201, -4.27403) (2.942526, -4.283698) (2.962993, -4.29322) (2.9836, -4.302596) (3.004345, -4.311826) (3.025227, -4.320909) (3.046244, -4.329847) (3.067395, -4.338637) (3.088677, -4.347282) (3.110089, -4.355781) (3.131628, -4.364134) (3.153293, -4.372342) (3.175083, -4.380404) (3.196995, -4.38832) (3.219028, -4.396091) (3.24118, -4.403715) (3.263451, -4.411194) (3.285839, -4.418527) (3.308341, -4.425714) (3.330957, -4.432755) (3.353685, -4.43965) (3.376524, -4.446398) (3.399472, -4.453) (3.422528, -4.459456) (3.445691, -4.465766) (3.468959, -4.471928) (3.492332, -4.477944) (3.515807, -4.483813) (3.539384, -4.489535) (3.56306, -4.495109) (3.586834, -4.500535) (3.610705, -4.505813) (3.634673, -4.510944) (3.658736, -4.515927) (3.678063, -4.519796) (3.692601, -4.522631) (3.702312, -4.524492) (3.707172, -4.525415) knots 0 0 0 0 0 0 0.01428571 0.02857143 0.04285714 0.05714286 0.07142857 0.08571429 0.1 0.11428571 0.12857143 0.14285714 0.15714286 0.17142857 0.18571429 0.2 0.21428571 0.22857143 0.24285714 0.25714286 0.27142857 0.28571429 0.3 0.31428571 0.32857143 0.34285714 0.35714286 0.37142857 0.38571429 0.4 0.41428571 0.42857143 0.44285714 0.45714286 0.47142857 0.48571429 0.5 0.51428571 0.52857143 0.54285714 0.55714286 0.57142857 0.58571429 0.6 0.61428571 0.62857143 0.64285714 0.65714286 0.67142857 0.68571429 0.7 0.71428571 0.72857143 0.74285714 0.75714286 0.77142857 0.78571429 0.8 0.81428571 0.82857143 0.84285714 0.85714286 0.87142857 0.88571429 0.9 0.91428571 0.92857143 0.94285714 0.95714286 0.97142857 0.98571429 1 1 1 1 1 1
  arc A9 (3.707172, -4.525415) -> (3.951767, -4.313472) centre (0, 0) ccw
  spline S9 degree 5 poles (3.951767, -4.313472) (3.951545, -4.30853) (3.951085, -4.298653) (3.950348, -4.283859) (3.949269, -4.264179) (3.947761, -4.239651) (3.946094, -4.215197) (3.944266, -4.190818) (3.942279, -4.166514) (3.940131, -4.142285) (3.937823, -4.118135) (3.935355, -4.094063) (3.932726, -4.070072) (3.929938, -4.046163) (3.926989, -4.022338) (3.92388, -3.998598) (3.920611, -3.974944) (3.917182, -3.951377) (3.913592, -3.9279) (3.909841, -3.904512) (3.90593, -3.881216) (3.901857, -3.858012) (3.897624, -3.834904) (3.893229, -3.811892) (3.888673, -3.788977) (3.883956, -3.766161) (3.879077, -3.743447) (3.874036, -3.720834) (3.868834, -3.698325) (3.863469, -3.675922) (3.857941, -3.653626) (3.852249, -3.631439) (3.846394, -3.609364) (3.840375, -3.587402) (3.834191, -3.565554) (3.827843, -3.543823) (3.821331, -3.522209) (3.814654, -3.500715) (3.807811, -3.479343) (3.800802, -3.458095) (3.793625, -3.436975) (3.786278, -3.415985) (3.77876, -3.39513) (3.77107, -3.37441) (3.763208, -3.353828) (3.755176, -3.333384) (3.746975, -3.313078) (3.738605, -3.292912) (3.730064, -3.272889) (3.721348, -3.253016) (3.71245, -3.233302) (3.703361, -3.213755) (3.694079, -3.194382) (3.684601, -3.175186) (3.674933, -3.156163) (3.665085, -3.137306) (3.655067, -3.118608) (3.644883, -3.100068) (3.634524, -3.081695) (3.623967, -3.063516) (3.613176, -3.045566) (3.602119, -3.027882) (3.590775, -3.010485) (3.579148, -2.993377) (3.567279, -2.976518) (3.55523, -2.959855) (3.543049, -2.943345) (3.530745, -2.926984) (3.518263, -2.910838) (3.505445, -2.895068) (3.492078, -2.879894) (3.480773, -2.86841) (3.471872, -2.860243) (3.465741, -2.855007) (3.462626, -2.852441) knots -1 -1 -1 -1 -1 -1 -0.98571429 -0.97142857 -0.95714286 -0.94285714 -0.92857143 -0.91428571 -0.9 -0.88571429 -0.87142857 -0.85714286 -0.84285714 -0.82857143 -0.81428571 -0.8 -0.78571429 -0.77142857 -0.75714286 -0.74285714 -0.72857143 -0.71428571 -0.7 -0.68571429 -0.67142857 -0.65714286 -0.64285714 -0.62857143 -0.61428571 -0.6 -0.58571429 -0.57142857 -0.55714286 -0.54285714 -0.52857143 -0.51428571 -0.5 -0.48571429 -0.47142857 -0.45714286 -0.44285714 -0.42857143 -0.41428571 -0.4 -0.38571429 -0.37142857 -0.35714286 -0.34285714 -0.32857143 -0.31428571 -0.3 -0.28571429 -0.27142857 -0.25714286 -0.24285714 -0.22857143 -0.21428571 -0.2 -0.18571429 -0.17142857 -0.15714286 -0.14285714 -0.12857143 -0.11428571 -0.1 -0.08571429 -0.07142857 -0.05714286 -0.04285714 -0.02857143 -0.01428571 0 0 0 0 0 0
  line L9 (3.462626, -2.852441) -> (3.016873, -2.485239)
  arc A10 (3.016873, -2.485239) -> (3.513907, -1.711839) centre (0, 0) ccw
  line L10 (3.513907, -1.711839) -> (4.033099, -1.964769)
  spline S10 degree 5 poles (4.033099, -1.964769) (4.036727, -1.966536) (4.044036, -1.969938) (4.055163, -1.974642) (4.070306, -1.980155) (4.089661, -1.98601) (4.10933, -1.991118) (4.129203, -1.995765) (4.149196, -2.000161) (4.169275, -2.004383) (4.189437, -2.008421) (4.209703, -2.012214) (4.230096, -2.015683) (4.250633, -2.018775) (4.271312, -2.021487) (4.292122, -2.023846) (4.313044, -2.025897) (4.33406, -2.027687) (4.355156, -2.02925) (4.376326, -2.030595) (4.397569, -2.031719) (4.418889, -2.032611) (4.440287, -2.033258) (4.461766, -2.033654) (4.483322, -2.033801) (4.504951, -2.033706) (4.526649, -2.033379) (4.54841, -2.03283) (4.570231, -2.032066) (4.592109, -2.031091) (4.614043, -2.029904) (4.636031, -2.028505) (4.658072, -2.026893) (4.680167, -2.025068) (4.702311, -2.023032) (4.724504, -2.020787) (4.746744, -2.018335) (4.769027, -2.015681) (4.791353, -2.012826) (4.813718, -2.009771) (4.836123, -2.006518) (4.858565, -2.003067) (4.881043, -1.999419) (4.903555, -1.995575) (4.926101, -1.991535) (4.948679, -1.987302) (4.971286, -1.982875) (4.993922, -1.978257) (5.016586, -1.973449) (5.039275, -1.968451) (5.061988, -1.963264) (5.084724, -1.957889) (5.107483, -1.952327) (5.130262, -1.946578) (5.15306, -1.940643) (5.175876, -1.934524) (5.198708, -1.92822) (5.221555, -1.921732) (5.244417, -1.915062) (5.267291, -1.908209) (5.290178, -1.901175) (5.313075, -1.89396) (5.335981, -1.886564) (5.358896, -1.878989) (5.381818, -1.871235) (5.404745, -1.863302) (5.427676, -1.855191) (5.45061, -1.846902) (5.473545, -1.838437) (5.496482, -1.829795) (5.519419, -1.820978) (5.537769, -1.813783) (5.551532, -1.808309) (5.560708, -1.804624) (5.565295, -1.802773) knots 0 0 0 0 0 0 0.01428571 0.02857143 0.04285714 0.05714286 0.07142857 0.08571429 0.1 0.11428571 0.12857143 0.14285714 0.15714286 0.17142857 0.18571429 0.2 0.21428571 0.22857143 0.24285714 0.25714286 0.27142857 0.28571429 0.3 0.31428571 0.32857143 0.34285714 0.35714286 0.37142857 0.38571429 0.4 0.41428571 0.42857143 0.44285714 0.45714286 0.47142857 0.48571429 0.5 0.51428571 0.52857143 0.54285714 0.55714286 0.57142857 0.58571429 0.6 0.61428571 0.62857143 0.64285714 0.65714286 0.67142857 0.68571429 0.7 0.71428571 0.72857143 0.74285714 0.75714286 0.77142857 0.78571429 0.8 0.81428571 0.82857143 0.84285714 0.85714286 0.87142857 0.88571429 0.9 0.91428571 0.92857143 0.94285714 0.95714286 0.97142857 0.98571429 1 1 1 1 1 1
  arc A11 (5.565295, -1.802773) -> (5.656477, -1.492237) centre (0, 0) ccw
  spline S11 degree 5 poles (5.656477, -1.492237) (5.653618, -1.488199) (5.647891, -1.480139) (5.639273, -1.468092) (5.627726, -1.452119) (5.613197, -1.432301) (5.598573, -1.41263) (5.583855, -1.393109) (5.569043, -1.373737) (5.554138, -1.354517) (5.539139, -1.335448) (5.524049, -1.316532) (5.508867, -1.29777) (5.493595, -1.279165) (5.478234, -1.260716) (5.462783, -1.242425) (5.447245, -1.224293) (5.431619, -1.206322) (5.415906, -1.188512) (5.400106, -1.170865) (5.384221, -1.153381) (5.36825, -1.136063) (5.352195, -1.118912) (5.336057, -1.101929) (5.319836, -1.085115) (5.303532, -1.068472) (5.287147, -1.052) (5.270681, -1.035702) (5.254135, -1.01958) (5.23751, -1.003633) (5.220805, -0.987865) (5.204022, -0.972278) (5.187162, -0.956873) (5.170225, -0.941651) (5.153211, -0.926615) (5.136122, -0.911765) (5.118958, -0.897104) (5.10172, -0.882632) (5.08441, -0.868352) (5.067026, -0.854266) (5.04957, -0.840379) (5.032041, -0.826693) (5.014441, -0.813213) (4.99677, -0.79994) (4.979028, -0.786876) (4.961218, -0.774019) (4.943341, -0.761371) (4.925397, -0.748931) (4.907387, -0.736704) (4.889311, -0.724698) (4.871166, -0.712925) (4.852953, -0.701394) (4.83467, -0.690115) (4.816318, -0.679091) (4.797901, -0.668315) (4.779422, -0.657775) (4.760885, -0.647461) (4.742294, -0.637371) (4.723646, -0.627515) (4.704936, -0.617929) (4.686155, -0.608663) (4.667292, -0.599764) (4.648344, -0.591262) (4.629312, -0.583155) (4.610213, -0.57539) (4.591068, -0.567886) (4.571894, -0.560582) (4.552699, -0.553471) (4.533469, -0.546636) (4.51416, -0.5403) (4.494712, -0.534761) (4.478992, -0.531212) (4.467089, -0.529154) (4.4591, -0.528064) (4.455093, -0.527589) knots -1 -1 -1 -1 -1 -1 -0.98571429 -0.97142857 -0.95714286 -0.94285714 -0.92857143 -0.91428571 -0.9 -0.88571429 -0.87142857 -0.85714286 -0.84285714 -0.82857143 -0.81428571 -0.8 -0.78571429 -0.77142857 -0.75714286 -0.74285714 -0.72857143 -0.71428571 -0.7 -0.68571429 -0.67142857 -0.65714286 -0.64285714 -0.62857143 -0.61428571 -0.6 -0.58571429 -0.57142857 -0.55714286 -0.54285714 -0.52857143 -0.51428571 -0.5 -0.48571429 -0.47142857 -0.45714286 -0.44285714 -0.42857143 -0.41428571 -0.4 -0.38571429 -0.37142857 -0.35714286 -0.34285714 -0.32857143 -0.31428571 -0.3 -0.28571429 -0.27142857 -0.25714286 -0.24285714 -0.22857143 -0.21428571 -0.2 -0.18571429 -0.17142857 -0.15714286 -0.14285714 -0.12857143 -0.11428571 -0.1 -0.08571429 -0.07142857 -0.05714286 -0.04285714 -0.02857143 -0.01428571 0 0 0 0 0 0
  line L11 (4.455093, -0.527589) -> (3.881577, -0.459671)
  arc A12 (3.881577, -0.459671) -> (3.881577, 0.459671) centre (0, 0) ccw
  line L12 (3.881577, 0.459671) -> (4.455093, 0.527589)
  spline S12 degree 5 poles (4.455093, 0.527589) (4.4591, 0.528064) (4.467089, 0.529154) (4.478992, 0.531212) (4.494712, 0.534761) (4.51416, 0.5403) (4.533469, 0.546636) (4.552699, 0.553471) (4.571894, 0.560582) (4.591068, 0.567886) (4.610213, 0.57539) (4.629312, 0.583155) (4.648344, 0.591262) (4.667292, 0.599764) (4.686155, 0.608663) (4.704936, 0.617929) (4.723646, 0.627515) (4.742294, 0.637371) (4.760885, 0.647461) (4.779422, 0.657775) (4.797901, 0.668315) (4.816318, 0.679091) (4.83467, 0.690115) (4.852953, 0.701394) (4.871166, 0.712925) (4.889311, 0.724698) (4.907387, 0.736704) (4.925397, 0.748931) (4.943341, 0.761371) (4.961218, 0.774019) (4.979028, 0.786876) (4.99677, 0.79994) (5.014441, 0.813213) (5.032041, 0.826693) (5.04957, 0.840379) (5.067026, 0.854266) (5.08441, 0.868352) (5.10172, 0.882632) (5.118958, 0.897104) (5.136122, 0.911765) (5.153211, 0.926615) (5.170225, 0.941651) (5.187162, 0.956873) (5.204022, 0.972278) (5.220805, 0.987865) (5.23751, 1.003633) (5.254135, 1.01958) (5.270681, 1.035702) (5.287147, 1.052) (5.303532, 1.068472) (5.319836, 1.085115) (5.336057, 1.101929) (5.352195, 1.118912) (5.36825, 1.136063) (5.384221, 1.153381) (5.400106, 1.170865) (5.415906, 1.188512) (5.431619, 1.206322) (5.447245, 1.224293) (5.462783, 1.242425) (5.478234, 1.260716) (5.493595, 1.279165) (5.508867, 1.29777) (5.524049, 1.316532) (5.539139, 1.335448) (5.554138, 1.354517) (5.569043, 1.373737) (5.583855, 1.393109) (5.598573, 1.41263) (5.613197, 1.432301) (5.627726, 1.452119) (5.639273, 1.468092) (5.647891, 1.480139) (5.653618, 1.488199) (5.656477, 1.492237) knots 0 0 0 0 0 0 0.01428571 0.02857143 0.04285714 0.05714286 0.07142857 0.08571429 0.1 0.11428571 0.12857143 0.14285714 0.15714286 0.17142857 0.18571429 0.2 0.21428571 0.22857143 0.24285714 0.25714286 0.27142857 0.28571429 0.3 0.31428571 0.32857143 0.34285714 0.35714286 0.37142857 0.38571429 0.4 0.41428571 0.42857143 0.44285714 0.45714286 0.47142857 0.48571429 0.5 0.51428571 0.52857143 0.54285714 0.55714286 0.57142857 0.58571429 0.6 0.61428571 0.62857143 0.64285714 0.65714286 0.67142857 0.68571429 0.7 0.71428571 0.72857143 0.74285714 0.75714286 0.77142857 0.78571429 0.8 0.81428571 0.82857143 0.84285714 0.85714286 0.87142857 0.88571429 0.9 0.91428571 0.92857143 0.94285714 0.95714286 0.97142857 0.98571429 1 1 1 1 1 1
  arc A13 (5.656477, 1.492237) -> (5.565295, 1.802773) centre (0, 0) ccw